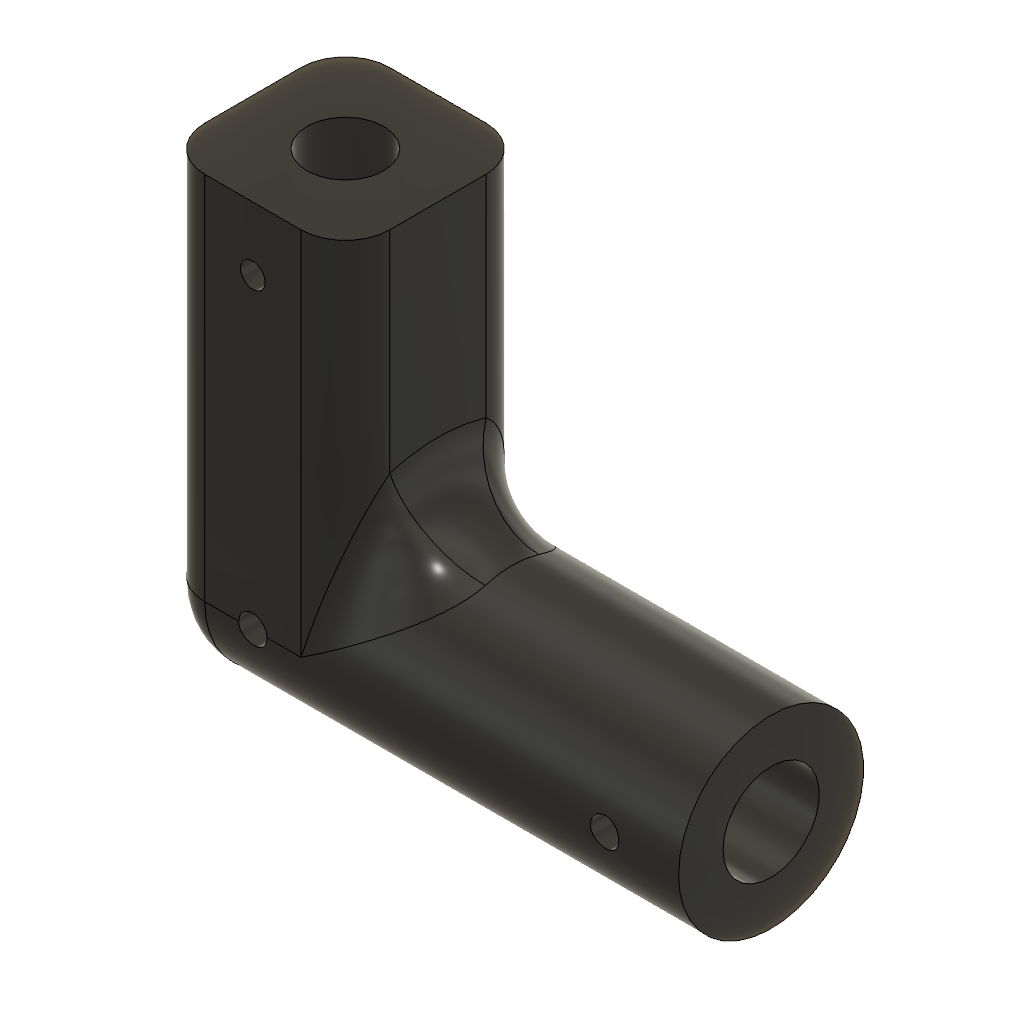
Codo_pendulo_2 (Autodesk Fusion 360 design; units mm, degrees)
Autodesk Fusion 360 part; units mm, degrees
sketch "Boceto1" plane through (0, 0, 0) normal (1, 0, 0) x (0, 0, -1)
  circle A0 centre (0, 0) radius 6.5
  circle A1 centre (0, 0) radius 12.5
  dimension "d1" = 13
  dimension "d2" = 25
  constraint coincident A0.centre A1.centre
  measures "d1" diameter of A0
  measures "d2" diameter of A1
extrude "Extruir1" add sketch "Boceto1" along normal blind 70
sketch "Boceto2" plane through (0, 0, 0) normal (-1, 0, 0) x (0, 0, 1)
  circle A0 centre (0, 0) radius 6.5
  circle A1 centre (0, 0) radius 12.5
  line L0 (-12.5, 0) -> (12.5, 0)
  line L1 (12.5, 0) -> (12.5, 50)
  line L2 (12.5, 50) -> (-12.5, 50)
  line L3 (-12.5, 50) -> (-12.5, 0)
  dimension "d5" = 25
  dimension "d6" = 50
  constraint horizontal L0
  constraint vertical L1
  constraint horizontal L2
  constraint vertical L3
  constraint coincident A1 L0.start
  measures "d5" distance of L0.start L0.end
  measures "d6" distance of L0.start L2.end
extrude "Extruir2" add sketch "Boceto2" against normal blind 25 contours A1 L1 L2 L3
sketch "Boceto3" plane through (0, 50, 0) normal (0, 1, 0) x (-1, 0, 0)
  line L0 (0, -12.5) -> (0, 12.5)
  line L1 (0, 12.5) -> (-25, 12.5)
  line L2 (-25, 12.5) -> (-25, -12.5)
  line L3 (-25, -12.5) -> (0, -12.5)
  circle A0 centre (-12.5, 0) radius 5.2
  dimension "d9" = 10.4
  measures "d9" diameter of A0
extrude "Extruir3" cut sketch "Boceto3" against normal blind 35 contours A0
fillet "Empalme1" radius 6 3 edges at (0, 25, -12.5) (0, -12.5, 0) (0, 25, 12.5)
fillet "Empalme1" radius 6 2 edges at (25, 25, -12.5) (25, 25, 12.5)
fillet "Empalme2" radius 10 3 edges at (22.9076, 5.8382, -11.0516) (25, 12.5, 0) (22.9076, 5.8382, 11.0516)
ref_plane "PlanoDeObra1" through (59.5576, 0, 12.5) normal (0, 0, 1) x (0, 1, 0)
sketch "Boceto4" plane through (0, 0, 12.5) normal (0, 0, 1) x (1, 0, 0)
  circle A0 centre (60, 0) radius 1.925
  circle A1 centre (12.5, 0) radius 1.925
  circle A2 centre (12.5, 41.4419) radius 1.669
  dimension "d19" = 3.85
  dimension "d20" = 60
  dimension "d23" = 3.85
  dimension "d24" = 12.5
  measures "d19" diameter of A0
  measures "d20" distance of origin A0.centre
  measures "d23" diameter of A1
  measures "d24" distance of origin A1.centre
extrude "Extruir4" cut sketch "Boceto4" against normal blind 25
equation "d24 = ( 25 / 2 ) * 1 mm"
